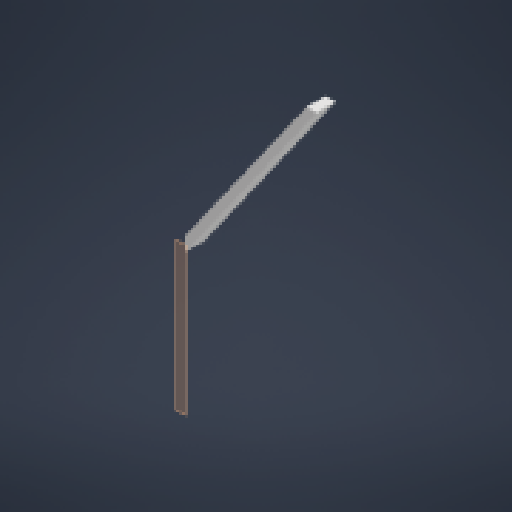
# Autodesk Inventor part: Lower Ear Diagonals
Saved by Autodesk Inventor 2027 (Build 310192000, 192)
## iProperties
Created: 2026-10-18
Part Number: Lower Ear Diagonals
Material: Generic
Document SubType Name: Modeling
Designer: lucas
Density: 1 g/cm^3
Appearance: Default
Author: lucas
Autodesk Inventor part; units mm, degrees
ref_plane "YZ Plane" through (0, 0, 0) normal (1, 0, 0) x (0, 1, 0)
ref_plane "XZ Plane" through (0, 0, 0) normal (0, 1, 0) x (-1, 0, 0)
ref_plane "XY Plane" through (0, 0, 0) normal (0, 0, 1) x (1, 0, 0)
ref_plane "Work Plane1" through (0, 0, 0) normal (0, 0, 1) x (1, 0, 0)
sketch "Sketch1" plane through (0, 0, 0) normal (0, 0, 1) x (1, 0, 0)
  line L0 (38.9946, 622.3) -> (647.7, 1485.9)
  line L1 (601.0869, 1485.9) -> (38.9946, 688.4323)
  line L2 (38.9946, 688.4323) -> (38.9946, 622.3)
  line L3 (601.0869, 1485.9) -> (647.7, 1485.9)
  point P0 (0, 0)
  dimension "d0" = 38.1
  constraints: 8 end point, 1 horizontal, 1 parallel, 1 vertical, 2 other
  measures "d0" distance between parallel lines of L0 L1
extrude "Extrusion1" add sketch "Sketch1" against normal blind 88.9
body "Solid1"
